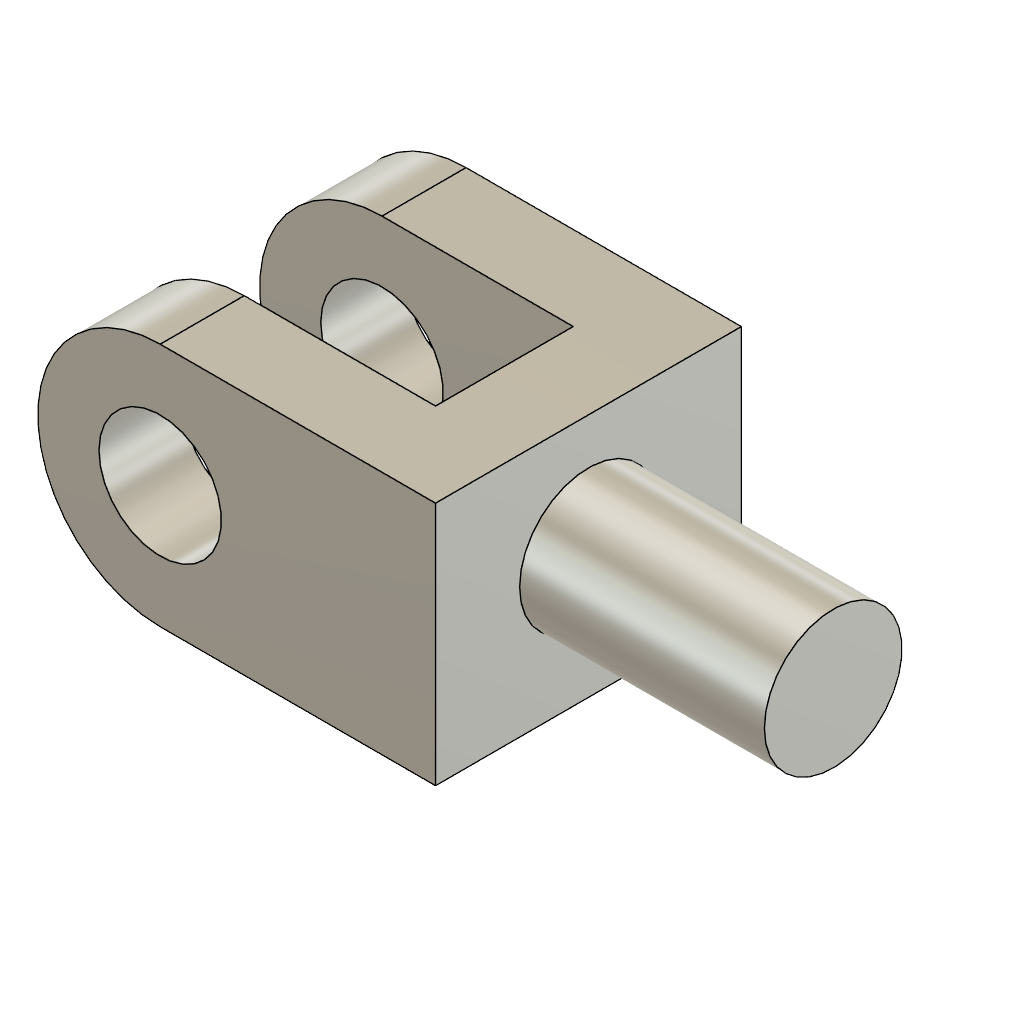
EX 3.1_ (Autodesk Fusion 360 design; units mm, degrees)
part number: 2026-11-18-21-40-52-490
Autodesk Fusion 360 part; units mm, degrees
sketch "Sketch1" plane through (0, 0, 0) normal (0, 1, 0) x (1, 0, 0)
  line L0 (-40, 9) -> (-40, 20)
  line L1 (-40, 20) -> (12, 20)
  line L2 (12, 20) -> (12, -20)
  line L3 (12, -20) -> (-40, -20)
  line L4 (-40, -20) -> (-40, -9)
  line L5 (-40, -9) -> (1, -9)
  line L6 (-40, 9) -> (1, 9)
  line L7 (1, 9) -> (1, -9)
  dimension "d1" = 11
  dimension "d2" = 52
  dimension "d3" = 40
  dimension "d4" = 11
  dimension "d5" = 41
  dimension "d6" = 41
  dimension "d7" = 9
  constraint vertical L0
  constraint perpendicular L0 L1
  constraint perpendicular L1 L2
  constraint perpendicular L2 L3
  constraint perpendicular L3 L4
  constraint perpendicular L4 L5
  constraint perpendicular L0 L6
  constraint perpendicular L6 L7
  measures "d1" distance of L0.start L0.end
  measures "d2" distance of L0.end L1.end
  measures "d3" distance of L1.end L2.end
  measures "d4" distance of L3.end L4.end
  measures "d5" distance of L4.end L5.end
  measures "d6" distance of L0.start L6.end
  measures "d7" distance of origin L6
extrude "Extrude1" add sketch "Sketch1" along normal blind 32
sketch "Sketch2" plane through (12, 0, 0) normal (1, 0, 0) x (0, 0, -1)
  line L0 (-20, 0) -> (20, 0)
  line L1 (20, 0) -> (20, 32)
  line L2 (20, 32) -> (-20, 32)
  line L3 (-20, 32) -> (-20, 0)
  circle A0 centre (0, 17) radius 9
  dimension "d10" = 18
  measures "d10" diameter of A0
extrude "Extrude2" add sketch "Sketch2" along normal blind 32 contours A0
sketch "Sketch3" plane through (0, 0, 20) normal (0, 0, 1) x (1, 0, 0)
  line L0 (-40, 0) -> (12, 0)
  line L1 (12, 0) -> (12, 32)
  line L2 (12, 32) -> (-40, 32)
  line L3 (-40, 32) -> (-40, 0)
  circle A0 centre (-24, 16) radius 8
  dimension "d13" = 16
  dimension "d14" = 36
  measures "d13" diameter of A0
  measures "d14" distance of L1 A0.centre
extrude "Extrude3" cut sketch "Sketch3" against normal blind 91 contours A0
fillet "Fillet1" radius 16 4 edges at (-40, 32, -14.5) (-40, 0, -14.5) (-40, 32, 14.5) (-40, 0, 14.5)
